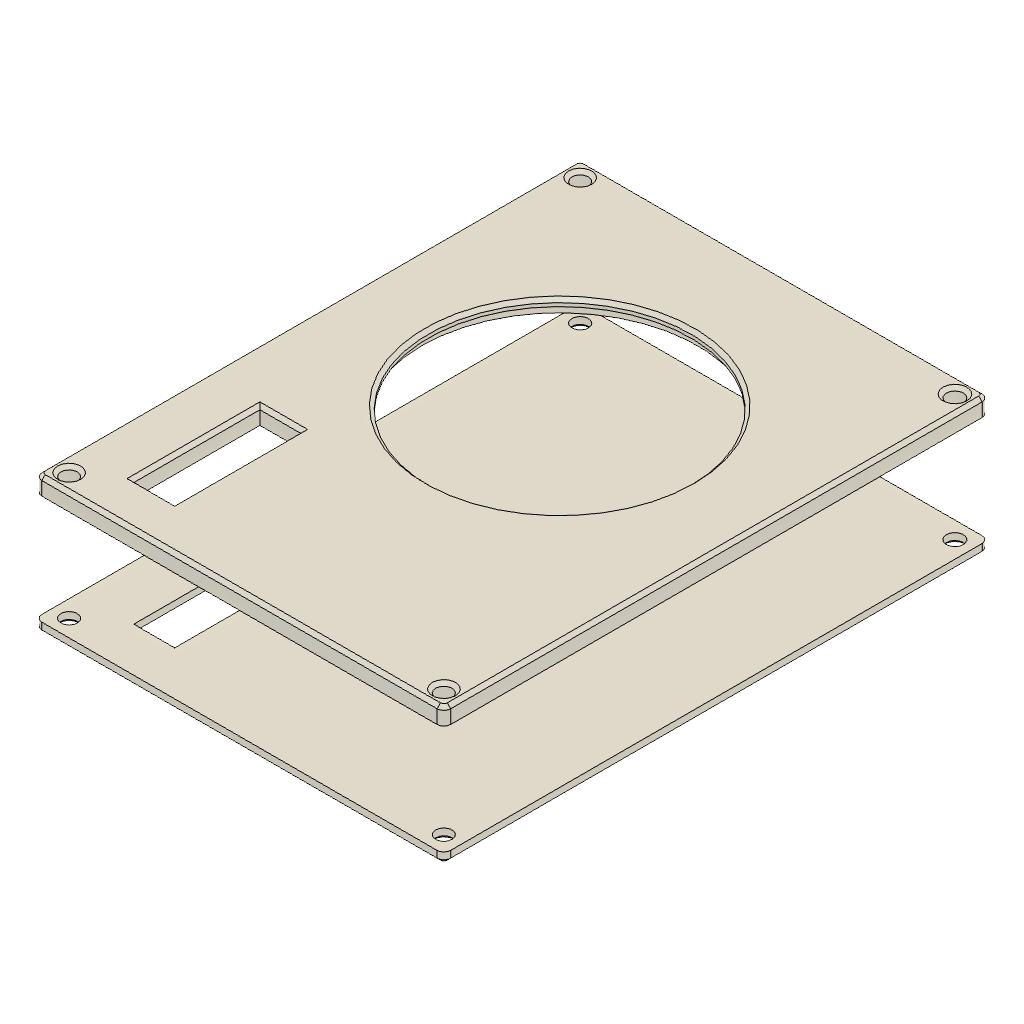
hikyaku (Autodesk Fusion 360 design; units mm, degrees)
part number: 2026-10-16-15-19-24-337
part number: 2026-10-17-19-43-08-700
part number: 2026-10-17-19-43-18-944
Autodesk Fusion 360 part; units mm, degrees
sketch "スケッチ1" plane through (0, 0, 0) normal (0, 1, 0) x (1, 0, 0)
  line L0 (0, 0) -> (60, 0)
  line L1 (60, 0) -> (60, -80)
  line L2 (60, -80) -> (0, -80)
  line L3 (0, -80) -> (0, 0)
  circle A0 centre (57.5, -2.5) radius 1.25
  circle A1 centre (2.5, -2.5) radius 1.2
  circle A2 centre (2.5, -77.5) radius 1.2
  circle A3 centre (57.5, -77.5) radius 1.2
  line L4 (25, -30) -> (35, -30)
  line L5 (35, -30) -> (35, -50)
  line L6 (35, -50) -> (25, -50)
  line L7 (25, -50) -> (25, -30)
  dimension "d6" = 2.5
  dimension "d7" = 2.5
  dimension "d8" = 2.5
  dimension "d11" = 2.5
  dimension "d12" = 2.5
  dimension "d13" = 2.4
  dimension "d14" = 2.5
  dimension "d15" = 2.5
  dimension "d16" = 2.4
  dimension "d17" = 2.5
  dimension "d18" = 2.5
  dimension "d21" = 20
  dimension "d22" = 25
  dimension "d23" = 25
  dimension "d24" = 30
  constraint horizontal L0
  constraint vertical L1
  constraint horizontal L2
  constraint vertical L3
  constraint coincident L0.start L3.end
  constraint horizontal L4
  constraint vertical L5
  constraint horizontal L6
  constraint vertical L7
  measures "d6" diameter of A0
  measures "d7" distance of L0 A0.centre
  measures "d8" distance of L1 A0.centre
  measures "d11" distance of L3 A1.centre
  measures "d12" distance of L0 A1.centre
  measures "d13" diameter of A2
  measures "d14" distance of L2 A2.centre
  measures "d15" distance of L3 A2.centre
  measures "d16" diameter of A3
  measures "d17" distance of L2 A3.centre
  measures "d18" distance of L1 A3.centre
  measures "d21" distance of L4.start L6.end
  measures "d22" distance of L3 L7
  measures "d23" distance of L1 L5
  measures "d24" distance of L2 L6
sketch "スケッチ4" plane through (0, 0, 0) normal (0, 1, 0) x (1, 0, 0)
  circle A0 centre (2.5, -2.5) radius 1.2
  circle A1 centre (57.5, -2.5) radius 1.25
  circle A2 centre (57.5, -77.5) radius 1.2
  circle A3 centre (2.5, -77.5) radius 1.2
  point P0 (2.5, -2.5)
  point P1 (57.5, -2.5)
  point P2 (57.5, -77.5)
  point P3 (2.5, -77.5)
extrude "押し出し4" add sketch "スケッチ1" along normal blind 1.5 makes body 1
sketch "スケッチ5" plane through (0, 1.5, 0) normal (0, 1, 0) x (-1, 0, 0)
  circle A0 centre (-57.5, 2.5) radius 1.25
  circle A1 centre (-57.5, 77.5) radius 1.2
  circle A2 centre (-2.5, 2.5) radius 1.2
  line L0 (-35, 50) -> (-25, 50)
  line L1 (-25, 50) -> (-25, 30)
  line L2 (-25, 30) -> (-35, 30)
  line L3 (-35, 30) -> (-35, 50)
  circle A3 centre (-2.5, 77.5) radius 1.2
  line L4 (0, 80) -> (-60, 80)
  line L5 (-60, 80) -> (-60, 0)
  line L6 (-60, 0) -> (0, 0)
  line L7 (0, 0) -> (0, 80)
  line L8 (0, 0) -> (-60, 0)
  line L9 (-60, 0) -> (-60, 80)
  line L10 (-60, 80) -> (0, 80)
  line L11 (0, 80) -> (0, 0)
  circle A4 centre (-30, 33) radius 19.25
  circle A5 centre (-30, 33) radius 20.25
  dimension "d27" = 38.5
  dimension "d28" = 30
  dimension "d29" = 47
  dimension "d30" = 40.5
  constraint horizontal L8
  constraint vertical L9
  constraint horizontal L10
  constraint vertical L11
  constraint coincident L4.end L5.start
  constraint coincident L6.end L7.start
  constraint concentric A4 A5
  measures "d27" diameter of A4
  measures "d28" distance of L9 A4.centre
  measures "d29" distance of L10 A4.centre
  measures "d30" diameter of A5
extrude "押し出し5" add sketch "スケッチ5" along normal blind 2 separate body contours L4 L5 L6 L7 L8 L9 L10 L11 | A5 makes body 2
extrude "押し出し6" cut sketch "スケッチ5" along normal blind 1.5 contours A5 bodies 2
extrude "押し出し7" add 1 faces at (29.5205, 3.5, 69.0654) along direction (0, 1, 0) blind 0.5 on bodies 2 bodies 2
sketch "スケッチ6" plane through (0, 0, 0) normal (0, 1, 0) x (1, 0, 0)
  line L0 (8, -55) -> (14, -55)
  line L1 (14, -55) -> (14, -73.5)
  line L2 (14, -73.5) -> (8, -73.5)
  line L3 (8, -73.5) -> (8, -55)
  line L4 (1, -79.75) -> (1, -50) construction
  line L5 (15, -79.75) -> (1, -79.75) construction
  line L6 (11, -57) -> (11, -66) construction
  line L7 (9.803, -64.25) -> (12.6514, -64.25) construction
  dimension "d37" = 6
  dimension "d38" = 18.5
  dimension "d40" = 3
  dimension "d42" = 9.25
  dimension "d43" = 10
  dimension "d44" = 15.5
  constraint horizontal L0
  constraint vertical L1
  constraint horizontal L2
  constraint vertical L3
  constraint parallel L1 L6
  constraint perpendicular L6 L7
  measures "d37" distance of L0.start L0.end
  measures "d38" distance of L0.start L2.end
  measures "d40" distance of L1 L6
  measures "d42" distance of L2 L7
  measures "d43" distance of L4 L6
  measures "d44" distance of L5 L7
extrude "押し出し8" cut sketch "スケッチ6" along normal blind 4 bodies 1 2
fillet "フィレット1" radius 1 8 edges at (0, 0.75, 80) (60, 0.75, 80) (60, 0.75, 0) (0, 0.75, 0) (0, 2.75, 80) (60, 2.75, 80) (60, 2.75, 0) (0, 2.75, 0) on bodies 1 2
chamfer "面取り1" distance 0.5 angle 45 1 faces at (33.9183, 4, 67.6662) tangent chain off on bodies 2
chamfer "面取り2" distance 0.5 angle 45 1 faces at (28.3167, 0, 11.6667) tangent chain off on bodies 1
copy_body "ボディ -> コンポーネント1" bodies 1 removing the originals makes body 3 in component "Buttom"
copy_body "ボディ -> コンポーネント2" bodies 2 removing the originals makes body 4 in component "Top"
component "Buttom" placed x (1, 0, 0) y (0, 1, 0) z (0, 0, 1) at (0, 0, 0)
component "Top" placed x (1, 0, 0) y (0, 1, 0) z (0, 0, 1) at (0, 0, 0)
equation "d22 = ( ( 60 - 10 ) / 2 ) * 1 mm"
equation "d23 = ( ( 60 - 10 ) / 2 ) * 1 mm"
equation "d40 = ( 6 / 2 ) * 1 mm"
equation "d42 = ( 18.5 / 2 ) * 1 mm"
equation "d55 = deg"
named bodies: "Buttom", "Top"
